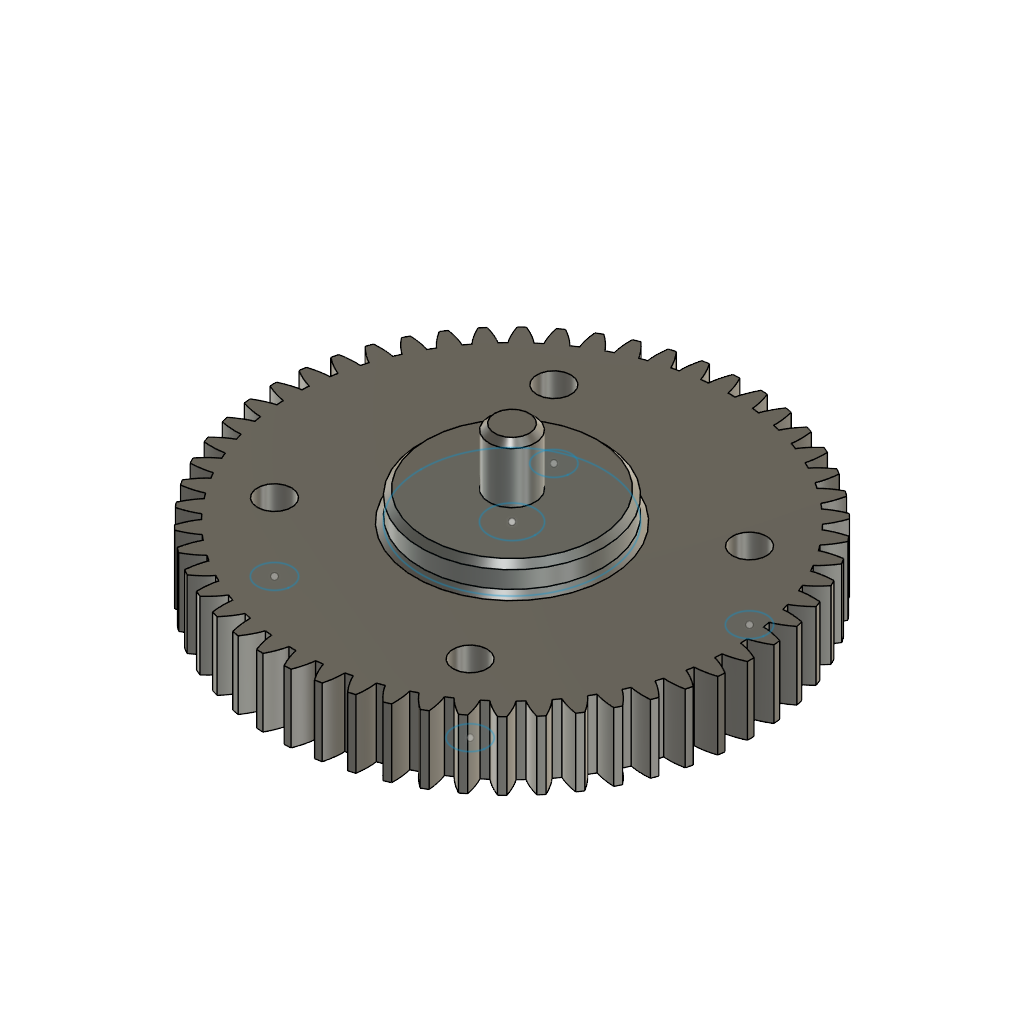
54T gear (Autodesk Fusion 360 design; units mm, degrees)
part number: 2026-11-12-16-14-11-418
Autodesk Fusion 360 part; units mm, degrees
sketch "Sketch1" plane through (0, 0, 0) normal (0, 0, 1) x (1, 0, 0)
  spline S0 degree 5 poles (38.0225, -1.6738) (38.0227, -1.6738) (38.0232, -1.6738) (38.024, -1.6739) (38.0253, -1.6739) (38.0272, -1.6739) (38.0295, -1.674) (38.032, -1.674) (38.0349, -1.6741) (38.038, -1.6741) (38.0414, -1.6742) (38.0451, -1.6742) (38.0491, -1.6743) (38.0533, -1.6743) (38.0578, -1.6743) (38.0625, -1.6743) (38.0675, -1.6742) (38.0727, -1.6742) (38.0781, -1.6742) (38.0838, -1.6741) (38.0897, -1.674) (38.0958, -1.6739) (38.1021, -1.6738) (38.1086, -1.6736) (38.1154, -1.6735) (38.1223, -1.6733) (38.1294, -1.673) (38.1368, -1.6728) (38.1443, -1.6725) (38.152, -1.6722) (38.1599, -1.6719) (38.1679, -1.6716) (38.1762, -1.6712) (38.1846, -1.6708) (38.1932, -1.6704) (38.202, -1.6699) (38.211, -1.6694) (38.2201, -1.6689) (38.2293, -1.6683) (38.2388, -1.6678) (38.2484, -1.6671) (38.2581, -1.6665) (38.268, -1.6658) (38.2781, -1.6651) (38.2883, -1.6643) (38.2986, -1.6636) (38.3091, -1.6627) (38.3198, -1.6619) (38.3305, -1.661) (38.3415, -1.6601) (38.3525, -1.6591) (38.3637, -1.6581) (38.3751, -1.6571) (38.3865, -1.656) (38.3981, -1.6549) (38.4099, -1.6537) (38.4217, -1.6525) (38.4337, -1.6513) (38.4458, -1.65) (38.4581, -1.6487) (38.4704, -1.6473) (38.4829, -1.646) (38.4955, -1.6445) (38.5083, -1.643) (38.5211, -1.6415) (38.5341, -1.64) (38.5472, -1.6384) (38.5604, -1.6367) (38.5737, -1.6351) (38.5871, -1.6333) (38.6006, -1.6316) (38.6142, -1.6298) (38.628, -1.6279) (38.6418, -1.626) (38.6558, -1.6241) (38.6699, -1.6221) (38.684, -1.6201) (38.6983, -1.618) (38.7127, -1.6159) (38.7272, -1.6137) (38.7418, -1.6115) (38.7564, -1.6093) (38.7712, -1.607) (38.7861, -1.6046) (38.8011, -1.6022) (38.8161, -1.5998) (38.8313, -1.5973) (38.8466, -1.5948) (38.8619, -1.5922) (38.8773, -1.5896) (38.8929, -1.5869) (38.9085, -1.5842) (38.9242, -1.5815) (38.94, -1.5787) (38.9559, -1.5758) (38.9719, -1.5729) (38.988, -1.57) (39.0041, -1.567) (39.0204, -1.5639) (39.0367, -1.5609) (39.0531, -1.5577) (39.0696, -1.5545) (39.0862, -1.5513) (39.1029, -1.548) (39.1196, -1.5447) (39.1364, -1.5413) (39.1533, -1.5379) (39.1703, -1.5344) (39.1874, -1.5309) (39.2045, -1.5273) (39.2217, -1.5237) (39.239, -1.52) (39.2564, -1.5163) (39.2738, -1.5125) (39.2913, -1.5087) (39.3089, -1.5048) (39.3266, -1.5009) (39.3444, -1.4969) (39.3622, -1.4929) (39.3801, -1.4888) (39.398, -1.4847) (39.416, -1.4805) (39.4341, -1.4763) (39.4523, -1.472) (39.4706, -1.4677) (39.4889, -1.4633) (39.5072, -1.4589) (39.5257, -1.4544) (39.5442, -1.4499) (39.5628, -1.4453) (39.5814, -1.4407) (39.6002, -1.436) (39.6189, -1.4313) (39.6378, -1.4265) (39.6567, -1.4216) (39.6757, -1.4167) (39.6947, -1.4118) (39.7138, -1.4068) (39.733, -1.4018) (39.7522, -1.3967) (39.7715, -1.3915) (39.7908, -1.3863) (39.8102, -1.3811) (39.8297, -1.3758) (39.8492, -1.3704) (39.8688, -1.365) (39.8885, -1.3595) (39.9082, -1.354) (39.9279, -1.3485) (39.9478, -1.3429) (39.9676, -1.3372) (39.9876, -1.3315) (40.0076, -1.3257) (40.0276, -1.3199) (40.0477, -1.314) (40.0679, -1.308) (40.0881, -1.3021) (40.1084, -1.296) (40.1287, -1.2899) (40.1491, -1.2838) (40.1695, -1.2776) (40.19, -1.2713) (40.2105, -1.265) (40.2311, -1.2587) (40.2518, -1.2522) (40.2725, -1.2458) (40.2932, -1.2393) (40.314, -1.2327) (40.3348, -1.2261) (40.3557, -1.2194) (40.3767, -1.2126) (40.3977, -1.2059) (40.4187, -1.199) (40.4398, -1.1921) (40.461, -1.1852) (40.4822, -1.1782) (40.5034, -1.1711) (40.5247, -1.164) (40.546, -1.1568) (40.5674, -1.1496) (40.5888, -1.1424) (40.6103, -1.135) (40.6318, -1.1277) (40.6534, -1.1202) (40.675, -1.1127) (40.6967, -1.1052) (40.7184, -1.0976) (40.7401, -1.0899) (40.7619, -1.0822) (40.7837, -1.0745) (40.8056, -1.0667) (40.8275, -1.0588) (40.8495, -1.0509) (40.8715, -1.0429) (40.8935, -1.0349) (40.9156, -1.0268) (40.9377, -1.0186) (40.9599, -1.0104) (40.9821, -1.0022) (41.0044, -0.9939) (41.0267, -0.9855) (41.049, -0.9771) (41.0714, -0.9687) (41.0938, -0.9601) (41.1162, -0.9516) (41.1387, -0.9429) (41.1613, -0.9342) (41.1838, -0.9255) (41.2064, -0.9167) (41.2291, -0.9079) (41.2518, -0.899) (41.2745, -0.89) (41.2972, -0.881) (41.32, -0.8719) (41.3428, -0.8628) (41.3657, -0.8536) (41.3886, -0.8444) (41.4116, -0.8351) (41.4345, -0.8257) (41.4575, -0.8163) (41.4806, -0.8069) (41.5037, -0.7974) (41.5268, -0.7878) (41.5499, -0.7782) (41.5731, -0.7685) (41.5963, -0.7588) (41.6196, -0.749) (41.6428, -0.7392) (41.6662, -0.7293) (41.6895, -0.7193) (41.7129, -0.7093) (41.7363, -0.6993) (41.7597, -0.6891) (41.7832, -0.679) (41.8067, -0.6687) (41.8303, -0.6585) (41.8538, -0.6481) (41.8774, -0.6377) (41.9011, -0.6273) (41.9247, -0.6168) (41.9484, -0.6062) (41.9674, -0.5977) (41.9817, -0.5913) (41.9912, -0.5871) (41.9959, -0.5849) knots 0 0 0 0 0 0 0.00416667 0.00833333 0.0125 0.01666667 0.02083333 0.025 0.02916667 0.03333333 0.0375 0.04166667 0.04583333 0.05 0.05416667 0.05833333 0.0625 0.06666667 0.07083333 0.075 0.07916667 0.08333333 0.0875 0.09166667 0.09583333 0.1 0.10416667 0.10833333 0.1125 0.11666667 0.12083333 0.125 0.12916667 0.13333333 0.1375 0.14166667 0.14583333 0.15 0.15416667 0.15833333 0.1625 0.16666667 0.17083333 0.175 0.17916667 0.18333333 0.1875 0.19166667 0.19583333 0.2 0.20416667 0.20833333 0.2125 0.21666667 0.22083333 0.225 0.22916667 0.23333333 0.2375 0.24166667 0.24583333 0.25 0.25416667 0.25833333 0.2625 0.26666667 0.27083333 0.275 0.27916667 0.28333333 0.2875 0.29166667 0.29583333 0.3 0.30416667 0.30833333 0.3125 0.31666667 0.32083333 0.325 0.32916667 0.33333333 0.3375 0.34166667 0.34583333 0.35 0.35416667 0.35833333 0.3625 0.36666667 0.37083333 0.375 0.37916667 0.38333333 0.3875 0.39166667 0.39583333 0.4 0.40416667 0.40833333 0.4125 0.41666667 0.42083333 0.425 0.42916667 0.43333333 0.4375 0.44166667 0.44583333 0.45 0.45416667 0.45833333 0.4625 0.46666667 0.47083333 0.475 0.47916667 0.48333333 0.4875 0.49166667 0.49583333 0.5 0.50416667 0.50833333 0.5125 0.51666667 0.52083333 0.525 0.52916667 0.53333333 0.5375 0.54166667 0.54583333 0.55 0.55416667 0.55833333 0.5625 0.56666667 0.57083333 0.575 0.57916667 0.58333333 0.5875 0.59166667 0.59583333 0.6 0.60416667 0.60833333 0.6125 0.61666667 0.62083333 0.625 0.62916667 0.63333333 0.6375 0.64166667 0.64583333 0.65 0.65416667 0.65833333 0.6625 0.66666667 0.67083333 0.675 0.67916667 0.68333333 0.6875 0.69166667 0.69583333 0.7 0.70416667 0.70833333 0.7125 0.71666667 0.72083333 0.725 0.72916667 0.73333333 0.7375 0.74166667 0.74583333 0.75 0.75416667 0.75833333 0.7625 0.76666667 0.77083333 0.775 0.77916667 0.78333333 0.7875 0.79166667 0.79583333 0.8 0.80416667 0.80833333 0.8125 0.81666667 0.82083333 0.825 0.82916667 0.83333333 0.8375 0.84166667 0.84583333 0.85 0.85416667 0.85833333 0.8625 0.86666667 0.87083333 0.875 0.87916667 0.88333333 0.8875 0.89166667 0.89583333 0.9 0.90416667 0.90833333 0.9125 0.91666667 0.92083333 0.925 0.92916667 0.93333333 0.9375 0.94166667 0.94583333 0.95 0.95416667 0.95833333 0.9625 0.96666667 0.97083333 0.975 0.97916667 0.98333333 0.9875 0.99166667 0.99583333 1 1 1 1 1 1
  spline S1 degree 5 poles (38.0225, 1.6738) (38.0227, 1.6738) (38.0232, 1.6738) (38.024, 1.6739) (38.0253, 1.6739) (38.0272, 1.6739) (38.0295, 1.674) (38.032, 1.674) (38.0349, 1.6741) (38.038, 1.6741) (38.0414, 1.6742) (38.0451, 1.6742) (38.0491, 1.6743) (38.0533, 1.6743) (38.0578, 1.6743) (38.0625, 1.6743) (38.0675, 1.6742) (38.0727, 1.6742) (38.0781, 1.6742) (38.0838, 1.6741) (38.0897, 1.674) (38.0958, 1.6739) (38.1021, 1.6738) (38.1086, 1.6736) (38.1154, 1.6735) (38.1223, 1.6733) (38.1294, 1.673) (38.1368, 1.6728) (38.1443, 1.6725) (38.152, 1.6722) (38.1599, 1.6719) (38.1679, 1.6716) (38.1762, 1.6712) (38.1846, 1.6708) (38.1932, 1.6704) (38.202, 1.6699) (38.211, 1.6694) (38.2201, 1.6689) (38.2293, 1.6683) (38.2388, 1.6678) (38.2484, 1.6671) (38.2581, 1.6665) (38.268, 1.6658) (38.2781, 1.6651) (38.2883, 1.6643) (38.2986, 1.6636) (38.3091, 1.6627) (38.3198, 1.6619) (38.3305, 1.661) (38.3415, 1.6601) (38.3525, 1.6591) (38.3637, 1.6581) (38.3751, 1.6571) (38.3865, 1.656) (38.3981, 1.6549) (38.4099, 1.6537) (38.4217, 1.6525) (38.4337, 1.6513) (38.4458, 1.65) (38.4581, 1.6487) (38.4704, 1.6473) (38.4829, 1.646) (38.4955, 1.6445) (38.5083, 1.643) (38.5211, 1.6415) (38.5341, 1.64) (38.5472, 1.6384) (38.5604, 1.6367) (38.5737, 1.6351) (38.5871, 1.6333) (38.6006, 1.6316) (38.6142, 1.6298) (38.628, 1.6279) (38.6418, 1.626) (38.6558, 1.6241) (38.6699, 1.6221) (38.684, 1.6201) (38.6983, 1.618) (38.7127, 1.6159) (38.7272, 1.6137) (38.7418, 1.6115) (38.7564, 1.6093) (38.7712, 1.607) (38.7861, 1.6046) (38.8011, 1.6022) (38.8161, 1.5998) (38.8313, 1.5973) (38.8466, 1.5948) (38.8619, 1.5922) (38.8773, 1.5896) (38.8929, 1.5869) (38.9085, 1.5842) (38.9242, 1.5815) (38.94, 1.5787) (38.9559, 1.5758) (38.9719, 1.5729) (38.988, 1.57) (39.0041, 1.567) (39.0204, 1.5639) (39.0367, 1.5609) (39.0531, 1.5577) (39.0696, 1.5545) (39.0862, 1.5513) (39.1029, 1.548) (39.1196, 1.5447) (39.1364, 1.5413) (39.1533, 1.5379) (39.1703, 1.5344) (39.1874, 1.5309) (39.2045, 1.5273) (39.2217, 1.5237) (39.239, 1.52) (39.2564, 1.5163) (39.2738, 1.5125) (39.2913, 1.5087) (39.3089, 1.5048) (39.3266, 1.5009) (39.3444, 1.4969) (39.3622, 1.4929) (39.3801, 1.4888) (39.398, 1.4847) (39.416, 1.4805) (39.4341, 1.4763) (39.4523, 1.472) (39.4706, 1.4677) (39.4889, 1.4633) (39.5072, 1.4589) (39.5257, 1.4544) (39.5442, 1.4499) (39.5628, 1.4453) (39.5814, 1.4407) (39.6002, 1.436) (39.6189, 1.4313) (39.6378, 1.4265) (39.6567, 1.4216) (39.6757, 1.4167) (39.6947, 1.4118) (39.7138, 1.4068) (39.733, 1.4018) (39.7522, 1.3967) (39.7715, 1.3915) (39.7908, 1.3863) (39.8102, 1.3811) (39.8297, 1.3758) (39.8492, 1.3704) (39.8688, 1.365) (39.8885, 1.3595) (39.9082, 1.354) (39.9279, 1.3485) (39.9478, 1.3429) (39.9676, 1.3372) (39.9876, 1.3315) (40.0076, 1.3257) (40.0276, 1.3199) (40.0477, 1.314) (40.0679, 1.308) (40.0881, 1.3021) (40.1084, 1.296) (40.1287, 1.2899) (40.1491, 1.2838) (40.1695, 1.2776) (40.19, 1.2713) (40.2105, 1.265) (40.2311, 1.2587) (40.2518, 1.2522) (40.2725, 1.2458) (40.2932, 1.2393) (40.314, 1.2327) (40.3348, 1.2261) (40.3557, 1.2194) (40.3767, 1.2126) (40.3977, 1.2059) (40.4187, 1.199) (40.4398, 1.1921) (40.461, 1.1852) (40.4822, 1.1782) (40.5034, 1.1711) (40.5247, 1.164) (40.546, 1.1568) (40.5674, 1.1496) (40.5888, 1.1424) (40.6103, 1.135) (40.6318, 1.1277) (40.6534, 1.1202) (40.675, 1.1127) (40.6967, 1.1052) (40.7184, 1.0976) (40.7401, 1.0899) (40.7619, 1.0822) (40.7837, 1.0745) (40.8056, 1.0667) (40.8275, 1.0588) (40.8495, 1.0509) (40.8715, 1.0429) (40.8935, 1.0349) (40.9156, 1.0268) (40.9377, 1.0186) (40.9599, 1.0104) (40.9821, 1.0022) (41.0044, 0.9939) (41.0267, 0.9855) (41.049, 0.9771) (41.0714, 0.9687) (41.0938, 0.9601) (41.1162, 0.9516) (41.1387, 0.9429) (41.1613, 0.9342) (41.1838, 0.9255) (41.2064, 0.9167) (41.2291, 0.9079) (41.2518, 0.899) (41.2745, 0.89) (41.2972, 0.881) (41.32, 0.8719) (41.3428, 0.8628) (41.3657, 0.8536) (41.3886, 0.8444) (41.4116, 0.8351) (41.4345, 0.8257) (41.4575, 0.8163) (41.4806, 0.8069) (41.5037, 0.7974) (41.5268, 0.7878) (41.5499, 0.7782) (41.5731, 0.7685) (41.5963, 0.7588) (41.6196, 0.749) (41.6428, 0.7392) (41.6662, 0.7293) (41.6895, 0.7193) (41.7129, 0.7093) (41.7363, 0.6993) (41.7597, 0.6891) (41.7832, 0.679) (41.8067, 0.6687) (41.8303, 0.6585) (41.8538, 0.6481) (41.8774, 0.6377) (41.9011, 0.6273) (41.9247, 0.6168) (41.9484, 0.6062) (41.9674, 0.5977) (41.9817, 0.5913) (41.9912, 0.5871) (41.9959, 0.5849) knots 0 0 0 0 0 0 0.00416667 0.00833333 0.0125 0.01666667 0.02083333 0.025 0.02916667 0.03333333 0.0375 0.04166667 0.04583333 0.05 0.05416667 0.05833333 0.0625 0.06666667 0.07083333 0.075 0.07916667 0.08333333 0.0875 0.09166667 0.09583333 0.1 0.10416667 0.10833333 0.1125 0.11666667 0.12083333 0.125 0.12916667 0.13333333 0.1375 0.14166667 0.14583333 0.15 0.15416667 0.15833333 0.1625 0.16666667 0.17083333 0.175 0.17916667 0.18333333 0.1875 0.19166667 0.19583333 0.2 0.20416667 0.20833333 0.2125 0.21666667 0.22083333 0.225 0.22916667 0.23333333 0.2375 0.24166667 0.24583333 0.25 0.25416667 0.25833333 0.2625 0.26666667 0.27083333 0.275 0.27916667 0.28333333 0.2875 0.29166667 0.29583333 0.3 0.30416667 0.30833333 0.3125 0.31666667 0.32083333 0.325 0.32916667 0.33333333 0.3375 0.34166667 0.34583333 0.35 0.35416667 0.35833333 0.3625 0.36666667 0.37083333 0.375 0.37916667 0.38333333 0.3875 0.39166667 0.39583333 0.4 0.40416667 0.40833333 0.4125 0.41666667 0.42083333 0.425 0.42916667 0.43333333 0.4375 0.44166667 0.44583333 0.45 0.45416667 0.45833333 0.4625 0.46666667 0.47083333 0.475 0.47916667 0.48333333 0.4875 0.49166667 0.49583333 0.5 0.50416667 0.50833333 0.5125 0.51666667 0.52083333 0.525 0.52916667 0.53333333 0.5375 0.54166667 0.54583333 0.55 0.55416667 0.55833333 0.5625 0.56666667 0.57083333 0.575 0.57916667 0.58333333 0.5875 0.59166667 0.59583333 0.6 0.60416667 0.60833333 0.6125 0.61666667 0.62083333 0.625 0.62916667 0.63333333 0.6375 0.64166667 0.64583333 0.65 0.65416667 0.65833333 0.6625 0.66666667 0.67083333 0.675 0.67916667 0.68333333 0.6875 0.69166667 0.69583333 0.7 0.70416667 0.70833333 0.7125 0.71666667 0.72083333 0.725 0.72916667 0.73333333 0.7375 0.74166667 0.74583333 0.75 0.75416667 0.75833333 0.7625 0.76666667 0.77083333 0.775 0.77916667 0.78333333 0.7875 0.79166667 0.79583333 0.8 0.80416667 0.80833333 0.8125 0.81666667 0.82083333 0.825 0.82916667 0.83333333 0.8375 0.84166667 0.84583333 0.85 0.85416667 0.85833333 0.8625 0.86666667 0.87083333 0.875 0.87916667 0.88333333 0.8875 0.89166667 0.89583333 0.9 0.90416667 0.90833333 0.9125 0.91666667 0.92083333 0.925 0.92916667 0.93333333 0.9375 0.94166667 0.94583333 0.95 0.95416667 0.95833333 0.9625 0.96666667 0.97083333 0.975 0.97916667 0.98333333 0.9875 0.99166667 0.99583333 1 1 1 1 1 1
  spline S2 degree 5 poles (38.0207, -1.6737) (38.0208, -1.6737) (38.0209, -1.6737) (38.0211, -1.6737) (38.0214, -1.6738) (38.0218, -1.6738) (38.022, -1.6738) (38.0222, -1.6738) (38.0224, -1.6738) (38.0225, -1.6738) knots 0 0 0 0 0 0 0.2 0.4 0.6 0.8 1 1 1 1 1 1
  spline S3 degree 5 poles (38.0207, 1.6737) (38.0208, 1.6737) (38.0209, 1.6737) (38.0211, 1.6737) (38.0214, 1.6738) (38.0218, 1.6738) (38.022, 1.6738) (38.0222, 1.6738) (38.0224, 1.6738) (38.0225, 1.6738) knots 0 0 0 0 0 0 0.2 0.4 0.6 0.8 1 1 1 1 1 1
  line L0 (0, 0) -> (38.0207, -1.6737)
  line L1 (0, 0) -> (38.0207, 1.6737)
  arc A0 (41.9959, -0.5849) -> (41.9959, 0.5849) centre (0, 0) ccw
  point P0 (38.0276, -1.6739)
  point P1 (38.0363, -1.6741)
  point P2 (38.0484, -1.6742)
  point P3 (38.0639, -1.6743)
  point P4 (38.0829, -1.6741)
  point P5 (38.1053, -1.6737)
  point P6 (38.1312, -1.673)
  point P7 (38.1606, -1.6719)
  point P8 (38.1934, -1.6704)
  point P9 (38.2296, -1.6683)
  point P10 (38.2692, -1.6657)
  point P11 (38.3123, -1.6625)
  point P12 (38.3587, -1.6585)
  point P13 (38.4086, -1.6538)
  point P14 (38.4618, -1.6483)
  point P15 (38.5185, -1.6418)
  point P16 (38.5785, -1.6344)
  point P17 (38.6418, -1.626)
  point P18 (38.7085, -1.6165)
  point P19 (38.7785, -1.6058)
  point P20 (38.8518, -1.5939)
  point P21 (38.9284, -1.5807)
  point P22 (39.0082, -1.5662)
  point P23 (39.0913, -1.5503)
  point P24 (39.1777, -1.5329)
  point P25 (39.2672, -1.5139)
  point P26 (39.36, -1.4934)
  point P27 (39.4559, -1.4712)
  point P28 (39.5549, -1.4472)
  point P29 (39.6571, -1.4215)
  point P30 (39.7623, -1.394)
  point P31 (39.8707, -1.3645)
  point P32 (39.982, -1.333)
  point P33 (40.0964, -1.2996)
  point P34 (40.2137, -1.264)
  point P35 (40.334, -1.2263)
  point P36 (40.4573, -1.1864)
  point P37 (40.5834, -1.1442)
  point P38 (40.7124, -1.0997)
  point P39 (40.8441, -1.0528)
  point P40 (40.9787, -1.0035)
  point P41 (41.1161, -0.9516)
  point P42 (41.2561, -0.8972)
  point P43 (41.3989, -0.8402)
  point P44 (41.5443, -0.7805)
  point P45 (41.6923, -0.7181)
  point P46 (41.8428, -0.6529)
  point P47 (38.0276, 1.6739)
  point P48 (38.0363, 1.6741)
  point P49 (38.0484, 1.6742)
  point P50 (38.0639, 1.6743)
  point P51 (38.0829, 1.6741)
  point P52 (38.1053, 1.6737)
  point P53 (38.1312, 1.673)
  point P54 (38.1606, 1.6719)
  point P55 (38.1934, 1.6704)
  point P56 (38.2296, 1.6683)
  point P57 (38.2692, 1.6657)
  point P58 (38.3123, 1.6625)
  point P59 (38.3587, 1.6585)
  point P60 (38.4086, 1.6538)
  point P61 (38.4618, 1.6483)
  point P62 (38.5185, 1.6418)
  point P63 (38.5785, 1.6344)
  point P64 (38.6418, 1.626)
  point P65 (38.7085, 1.6165)
  point P66 (38.7785, 1.6058)
  point P67 (38.8518, 1.5939)
  point P68 (38.9284, 1.5807)
  point P69 (39.0082, 1.5662)
  point P70 (39.0913, 1.5503)
  point P71 (39.1777, 1.5329)
  point P72 (39.2672, 1.5139)
  point P73 (39.36, 1.4934)
  point P74 (39.4559, 1.4712)
  point P75 (39.5549, 1.4472)
  point P76 (39.6571, 1.4215)
  point P77 (39.7623, 1.394)
  point P78 (39.8707, 1.3645)
  point P79 (39.982, 1.333)
  point P80 (40.0964, 1.2996)
  point P81 (40.2137, 1.264)
  point P82 (40.334, 1.2263)
  point P83 (40.4573, 1.1864)
  point P84 (40.5834, 1.1442)
  point P85 (40.7124, 1.0997)
  point P86 (40.8441, 1.0528)
  point P87 (40.9787, 1.0035)
  point P88 (41.1161, 0.9516)
  point P89 (41.2561, 0.8972)
  point P90 (41.3989, 0.8402)
  point P91 (41.5443, 0.7805)
  point P92 (41.6923, 0.7181)
  point P93 (41.8428, 0.6529)
sketch "Sketch2" plane through (0, 0, 0) normal (0, 0, 1) x (1, 0, 0)
  circle A0 centre (0, 0) radius 38.625
extrude "Extrude1" add sketch "Sketch2" along normal blind 12 makes body 1
extrude "Extrude2" add sketch "Sketch1" along normal blind 12 separate body makes body 2
pattern_circular "C-Pattern1" count 54 over 360 about axis through (0, 0, 1.75) along (0, 0, 1) of "Extrude2" makes body 3 at (12.5237, 2.0255, 4) makes body 4 at (12.4612, 2.38, 4) makes body 5 at (12.1006, 3.8105, 4) makes body 6 at (11.5764, 5.1896, 4) makes body 7 at (10.8957, 6.4984, 4) makes body 8 at (10.0676, 7.7194, 4) makes body 9 at (9.1034, 8.836, 4) makes body 10 at (7.1209, 10.4994, 4) makes body 11 at (5.8539, 11.2551, 4) makes body 12 at (5.5323, 11.4166, 4) makes body 13 at (4.1695, 11.9817, 4) makes body 14 at (1.6514, 12.5785, 4) makes body 15 at (0.1799, 12.6851, 4) makes body 16 at (-0.1799, 12.6851, 4) makes body 17 at (-1.6514, 12.5785, 4) makes body 18 at (-3.1005, 12.3017, 4) makes body 19 at (-4.5077, 11.8586, 4) makes body 20 at (-5.8539, 11.2551, 4) makes body 21 at (-7.1209, 10.4994, 4) makes body 22 at (-9.1034, 8.836, 4) makes body 23 at (-9.3503, 8.5742, 4) makes body 24 at (-10.2825, 7.4307, 4) makes body 25 at (-11.5764, 5.1896, 4) makes body 26 at (-11.719, 4.8591, 4) makes body 27 at (-12.2038, 3.4658, 4) makes body 28 at (-12.5237, 2.0255, 4) makes body 29 at (-12.6742, 0.5579, 4) makes body 30 at (-12.6532, -0.9172, 4) makes body 31 at (-12.4612, -2.38, 4) makes body 32 at (-12.1006, -3.8105, 4) makes body 33 at (-11.5764, -5.1896, 4) makes body 34 at (-10.8957, -6.4984, 4) makes body 35 at (-9.3503, -8.5742, 4) makes body 36 at (-8.2917, -9.6017, 4) makes body 37 at (-7.1209, -10.4994, 4) makes body 38 at (-6.8203, -10.6972, 4) makes body 39 at (-4.5077, -11.8586, 4) makes body 40 at (-4.1695, -11.9817, 4) makes body 41 at (-2.7503, -12.3847, 4) makes body 42 at (-1.2939, -12.6203, 4) makes body 43 at (0.1799, -12.6851, 4) makes body 44 at (2.7503, -12.3847, 4) makes body 45 at (3.1005, -12.3017, 4) makes body 46 at (4.5077, -11.8586, 4) makes body 47 at (5.8539, -11.2551, 4) makes body 48 at (7.1209, -10.4994, 4) makes body 49 at (8.2917, -9.6017, 4) makes body 50 at (9.3503, -8.5742, 4) makes body 51 at (20.565, -14.8614, 8) makes body 52 at (11.5764, -5.1896, 4) makes body 53 at (12.1006, -3.8105, 4) makes body 54 at (12.4612, -2.38, 4) makes body 55 at (12.5237, -2.0255, 4)
combine "Combine1" operation add target body 1 tool bodies 2 3 4 5 6 7 8 9 10 11 12 13 14 15 16 17 18 19 20 21 22 23 24 25 26 27 28 29 30 31 32 33 34 35 36 37 38 39 40 41 42 43 44 45 46 47 48 49 50 51 52 53 54 55
sketch "Sketch3" plane through (0, 0, 0) normal (0, 0, 1) x (1, 0, 0)
  line L0 (0, 0) -> (49.2129, 0) construction
  line L1 (49.2129, 0) -> (49.2129, 3) construction
  line L2 (49.2129, 3) -> (0, 3) construction
  line L3 (0, 3) -> (0, 0) construction
  constraint perpendicular L0 L1
  constraint parallel L0 L2
  constraint parallel L1 L3
sketch "sketch 3103" plane through (0, 0, 12) normal (0, 0, 1) x (-1, 0, 0)
  circle A0 centre (0, 0) radius 4.05
  circle A1 centre (0, 0) radius 16
extrude "Extrude3" add sketch "sketch 3103" along normal blind 5 bodies 1
extrude "Extrude4" add 1 faces at (1.2163, 0.5857, 12) along direction (0, 0, 1) blind 15 on bodies 1 bodies 1
chamfer "Chamfer1" distance 1 angle 45 1 edges at (-3.7759, -1.4645, 27) tangent chain off on bodies 1
chamfer "Chamfer1" distance 1 angle 45 1 edges at (14.9172, 5.7858, 17) tangent chain off on bodies 1
chamfer "Chamfer1" distance 1 angle 45 1 edges at (14.9172, -5.7858, 12) tangent chain off on bodies 1
sketch "sketch 3119" plane through (118.0388, -27.1598, 0) normal (0, 0, -1) x (0.984808, -0.173648, 0)
  circle A0 centre (-142.175, -27.4632) radius 3
  circle A1 centre (-99.7486, 14.9632) radius 3
  circle A2 centre (-142.175, 14.9632) radius 3
  circle A3 centre (-99.7486, -27.4632) radius 3
extrude "Extrude5" cut sketch "sketch 3119" against normal blind 12 bodies 1
chamfer "Chamfer2" [suppressed]
